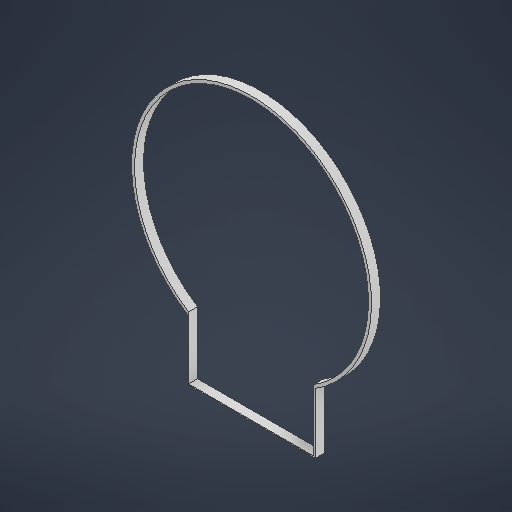
# Autodesk Inventor part: Zip tie
Saved by Autodesk Inventor 2026.2 (Build 302298010, 298A)
## iProperties
Created: 2026-10-06
Part Number: Zip tie
Material: Generisch
Document SubType Name: Modeling
Designer: denis
Mass: 0.715006 g
Surface Area: 21.9712 cm^2
Volume: 0.715006 cm^3
Density: 1 g/cm^3
Appearance: Vorgabe
Author: denis
Autodesk Inventor part; units mm, degrees
ref_plane "YZ Plane" through (0, 0, 0) normal (1, 0, 0) x (0, 1, 0)
ref_plane "XZ Plane" through (0, 0, 0) normal (0, 1, 0) x (-1, 0, 0)
ref_plane "XY Plane" through (0, 0, 0) normal (0, 0, 1) x (1, 0, 0)
sketch "Skizze1" plane through (0, 0, 0) normal (0, 0, 1) x (1, 0, 0)
  line L0 (0, -19.56) -> (0, 112.0835) construction
  line L1 (-54.7101, 0) -> (57.3643, 0) construction
  line L2 (22.647, 0) -> (22.647, 20)
  line L3 (-20, 0) -> (-20, 20)
  line L4 (-20, 0) -> (22.647, 0)
  line L5 (22.647, 0) -> (22.647, -0.7538)
  line L6 (22.647, -0.7538) -> (-20, -0.7538)
  line L7 (-20, -0.7538) -> (-20, 0)
  line L8 (-20, 0) -> (-19.3459, 0)
  arc A0 (21.947, 18.9743) -> (-19.3459, 19.0038) centre (1.3251, 53.2487) ccw
  line L9 (-19.3459, 0) -> (-19.3459, 19.0038)
  line L10 (22.647, 0) -> (21.947, 0)
  line L11 (21.947, 0) -> (21.947, 18.9743)
  line L12 (21.947, 20.1468) -> (21.947, 18.9743)
  arc A1 (21.947, 20.1468) -> (-19.3459, 20.1774) centre (1.3251, 53.2487) ccw
  line L13 (-19.3459, 19.0038) -> (-19.3459, 20.1774)
  point P0 (0, 0)
  point P1 (-20, 19.4073)
  point P2 (22.647, 19.4053)
  dimension "d13" = 20
  dimension "d16" = 80
  dimension "d17" = 0.7
  dimension "d23" = 78
  constraints: 24 end point, 6 vertical, 4 point on circle, 3 perpendicular, 3 point on line, 2 centre point, 1 coincident, 1 collinear
  measures "d13" distance of L2.start L2.end
  measures "d16" diameter of A0
  measures "d17" distance of L2.start L10.end
  measures "d23" diameter of A1
extrude "Extrusion6" add sketch "Skizze1" against normal blind 3
sketch "Skizze7" plane through (0, 0, 0) normal (0, 0, 1) x (1, 0, 0)
  arc A0 (22.647, 19.4053) -> (-20, 19.4073) centre (1.3251, 53.2487) ccw construction
  circle A1 centre (1.3251, 53.2487) radius 39
  point P0 (-19.3459, 19.5893)
  point P1 (19.3, 19.5612)
  point P2 (0, 0)
  dimension "d20" = 78
  constraints: 1 centre point, 1 coincident
  measures "d20" diameter of A1
extrude "Extrusion7" cut sketch "Skizze7" against normal blind 3
sketch "Skizze8" plane through (0, 0, 0) normal (0, 0, 1) x (1, 0, 0)
  line L0 (-19.6507, -0.4424) -> (21.9449, -0.4424)
  line L1 (21.9449, -0.4424) -> (21.9449, 21.8943)
  line L2 (21.9449, 21.8943) -> (-19.6507, 21.8943)
  line L3 (-19.6507, 21.8943) -> (-19.6507, -0.4424)
  point P0 (0, 0)
  constraints: 8 end point, 2 parallel, 1 horizontal, 1 perpendicular
extrude "Extrusion8" cut sketch "Skizze8" against normal blind 3
